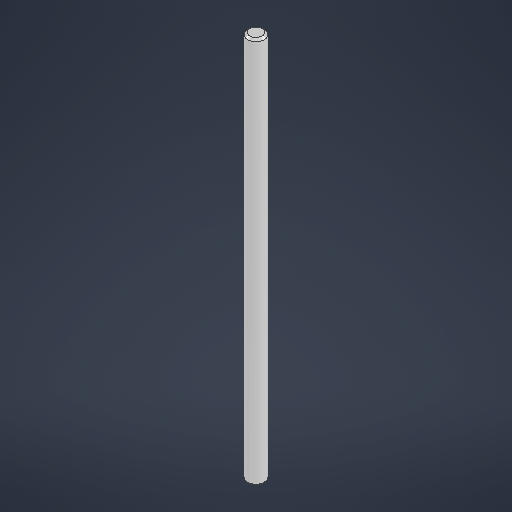
# Autodesk Inventor part: Linear Guide Rods
Saved by Autodesk Inventor 2027.1 (Build 311270010, 270A)
## iProperties
Created: 2026-10-04
Part Number: Linear Guide Rods
Material: Aluminum 6061
Document SubType Name: Modeling
Designer: Ahmed
Density: 2.7 g/cm^3
Appearance: Aluminum - Polished
Mass: 24.6383 g
Surface Area: 46.4264 cm^2
Volume: 9.12528 cm^3
Author: Ahmed
Autodesk Inventor part; units mm, degrees
ref_plane "YZ Plane" through (0, 0, 0) normal (1, 0, 0) x (0, 1, 0)
ref_plane "XZ Plane" through (0, 0, 0) normal (0, 1, 0) x (-1, 0, 0)
ref_plane "XY Plane" through (0, 0, 0) normal (0, 0, 1) x (1, 0, 0)
sketch "Sketch1" plane through (0, 0, 0) normal (0, 1, 0) x (-1, 0, 0)
  circle A0 centre (0, 0) radius 4
  dimension "d0" = 8
  constraints: 1 centre point, 1 coincident
  measures "d0" diameter of A0
extrude "Extrusion1" add sketch "Sketch1" along normal blind 182
chamfer "Chamfer1" distance 1 angle 45 2 edges at (4, 182, 0) (4, 0, 0)
body "Solid1"
